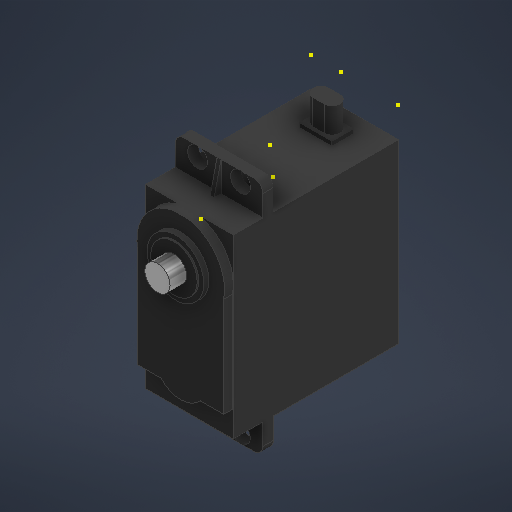
# Autodesk Inventor part: ServoMG99XX
Saved by Autodesk Inventor 2026.2 (Build 302298000, 298)
## iProperties
Created: 2026-07-16
Part Number: ServoMG99XX
Material: Generic
Document SubType Name: Modeling
Designer: Alexa
Density: 1 g/cm^3
Appearance: Default
Author: Alexa
Autodesk Inventor part; units mm, degrees
ref_plane "YZ Plane" through (0, 0, 0) normal (1, 0, 0) x (0, 1, 0)
ref_plane "XZ Plane" through (0, 0, 0) normal (0, 1, 0) x (-1, 0, 0)
ref_plane "XY Plane" through (0, 0, 0) normal (0, 0, 1) x (1, 0, 0)
sketch "Sketch1" plane through (0, 0, 0) normal (0, 0, 1) x (1, 0, 0)
  line L0 (0, 0) -> (-20, 0)
  line L1 (-20, 0) -> (-20, -54)
  line L2 (-20, -54) -> (0, -54)
  line L3 (0, -54) -> (0, 0)
  dimension "d0" = 20
  dimension "d1" = 54
  constraints: 8 end point, 2 parallel, 1 horizontal, 1 perpendicular
  measures "d0" distance of L2.end L1.end
  measures "d1" distance of L1.end L0.end
extrude "Extrusion1" add sketch "Sketch1" along normal blind 45
sketch "Sketch2" plane through (0, 0, 45) normal (0, 0, 1) x (1, 0, 0)
  point P0 (0, 0)
sketch "Sketch3" plane through (0, 0, 45) normal (0, 0, 1) x (1, 0, 0)
  point P0 (0, 0)
sketch "Sketch4" plane through (0, -54, 0) normal (1, 0, 0) x (0, 0, -1)
  line L0 (0, 54) -> (-28.52, 54)
  line L1 (-28.52, 54) -> (-28.52, 47.18)
  line L2 (-28.52, 47.18) -> (0, 47.18)
  line L3 (0, 47.18) -> (0, 54)
  line L4 (0, 54) -> (0, 0) projected
  line L5 (0, 0) -> (-28.52, 0)
  line L6 (-28.52, 0) -> (-28.52, 6.82)
  line L7 (-28.52, 6.82) -> (0, 6.82)
  line L8 (0, 6.82) -> (0, 0)
  line L9 (0, 54) -> (-45, 54) projected
  line L10 (-28.52, 47.18) -> (-32.52, 47.18)
  line L11 (-32.52, 47.18) -> (-32.52, 54)
  line L12 (-32.52, 54) -> (-28.52, 54)
  line L13 (-28.52, 54) -> (-28.52, 47.18)
  line L14 (0, 0) -> (-45, 0) projected
  line L15 (-28.52, 6.82) -> (-32.52, 6.82)
  line L16 (-32.52, 6.82) -> (-32.52, 0)
  line L17 (-32.52, 0) -> (-28.52, 0)
  line L18 (-28.52, 0) -> (-28.52, 6.82)
  line L19 (-32.52, 47.18) -> (-3.9, 47.18)
  line L20 (-3.9, 47.18) -> (-8.9, 47.18)
  line L21 (-8.9, 47.18) -> (-8.9, 54)
  line L22 (-8.9, 54) -> (-3.9, 54)
  line L23 (-3.9, 54) -> (-3.9, 47.18)
  line L24 (-32.52, 47.18) -> (-45, 47.18)
  line L25 (-45, 47.18) -> (-45, 54)
  line L26 (-45, 54) -> (-32.52, 54)
  line L27 (-32.52, 54) -> (-32.52, 47.18)
  line L28 (-32.52, 6.82) -> (-45, 6.82)
  line L29 (-45, 6.82) -> (-45, 0)
  line L30 (-45, 0) -> (-32.52, 0)
  line L31 (-32.52, 0) -> (-32.52, 6.82)
  line L32 (0, 47.18) -> (-41.22, 47.18)
  line L33 (-41.22, 47.18) -> (-41.22, 6.82)
  line L34 (-41.22, 6.82) -> (0, 6.82)
  line L35 (0, 6.82) -> (0, 47.18)
  line L36 (-45, 6.82) -> (-41.22, 6.82)
  line L37 (-41.22, 6.82) -> (-41.22, 40.24)
  line L38 (-41.22, 40.24) -> (-45, 40.24)
  line L39 (-45, 40.24) -> (-45, 6.82)
  line L40 (-45, 40.24) -> (-41.22, 40.24)
  line L41 (-41.22, 40.24) -> (-41.22, 34.46)
  line L42 (-41.22, 34.46) -> (-45, 34.46)
  line L43 (-45, 34.46) -> (-45, 40.24)
  line L44 (-45, 47.18) -> (-41.22, 47.18)
  line L45 (-41.22, 47.18) -> (-41.22, 40.24)
  line L46 (-41.22, 40.24) -> (-45, 40.24)
  line L47 (-45, 40.24) -> (-45, 47.18)
  line L48 (-45, 34.46) -> (-41.22, 34.46)
  line L49 (-41.22, 34.46) -> (-41.22, 6.82)
  line L50 (-41.22, 6.82) -> (-45, 6.82)
  line L51 (-45, 6.82) -> (-45, 34.46)
  line L52 (-45, 6.82) -> (0, 6.82)
  line L53 (0, 6.82) -> (0, 0)
  line L54 (0, 0) -> (-45, 0)
  line L55 (-45, 0) -> (-45, 6.82)
  line L56 (-45, 0) -> (-45, 54) projected
  line L57 (-45, 54) -> (-32.52, 54)
  line L58 (-32.52, 54) -> (-32.52, 47.18)
  line L59 (-32.52, 47.18) -> (-45, 47.18)
  line L60 (-45, 47.18) -> (-45, 54)
  line L61 (-28.52, 54) -> (-8.9, 54)
  line L62 (-8.9, 54) -> (-8.9, 47.18)
  line L63 (-8.9, 47.18) -> (-28.52, 47.18)
  line L64 (-28.52, 47.18) -> (-28.52, 54)
  line L65 (-3.9, 54) -> (0, 54)
  line L66 (0, 54) -> (0, 47.18)
  line L67 (0, 47.18) -> (-3.9, 47.18)
  line L68 (-3.9, 47.18) -> (-3.9, 54)
  point P0 (0, 6.82)
  dimension "d4" = 28.52
  dimension "d5" = 6.82
  dimension "d6" = 28.52
  dimension "d7" = 6.82
  dimension "d8" = 4
  dimension "d9" = 4
  dimension "d10" = 28.62
  dimension "d11" = 5
  dimension "d12" = 41.22
  dimension "d13" = 33.42
  dimension "d14" = 5.78
  constraints: 130 end point, 32 parallel, 16 horizontal, 16 perpendicular, 7 point on line, 1 other
  measures "d4" distance of L2.end L1.end
  measures "d5" distance of L1.end L0.end
  measures "d6" distance of L6.end L7.end
  measures "d7" distance of L5.end L6.end
  measures "d8" distance of L11.end L12.end
  measures "d9" distance of L17.end L16.end
  measures "d10" distance of L10.end L19.end
  measures "d11" distance of L21.end L22.end
  measures "d12" distance of L34.end L33.end
  measures "d13" distance of L37.end L36.end
  measures "d14" distance of L40.end L41.end
extrude "Extrusion2" cut sketch "Sketch4" against normal blind 45 contours L3 L2 L23 L0 | L21 L2 L1 L0 | L4 L5 L6 L7 | L11 L24 L25 L9 | L16 L14 L29 L28 | L28 L39 L42 L33 | L33 L38 L47 L24
sketch "Sketch5" plane through (0, -47.18, 0) normal (1, 0, 0) x (0, 0, -1)
  line L0 (-28.52, 40.36) -> (-28.52, 47.18) projected
  line L1 (-28.52, 47.18) -> (-30.92, 47.18)
  line L2 (-30.92, 47.18) -> (-30.92, 40.36)
  line L3 (-30.92, 40.36) -> (-28.52, 40.36)
  line L4 (-28.52, 40.36) -> (-28.52, 47.18)
  line L5 (-32.52, 47.18) -> (-32.52, 40.36) projected
  line L6 (-30.92, 47.18) -> (-32.52, 40.36)
  line L7 (-32.52, 40.36) -> (-32.52, 47.18)
  line L8 (-32.52, 47.18) -> (-30.92, 47.18)
  line L9 (-28.52, -6.82) -> (-32.52, -6.82) projected
  line L10 (-30.92, -6.82) -> (-30.92, 0.0312)
  line L11 (-30.92, 0.0312) -> (-32.5273, 0.0312)
  line L12 (-32.5273, 0.0312) -> (-30.92, -6.82)
  line L13 (-41.22, 0) -> (-32.52, 0) projected
  line L14 (-32.52, 0) -> (-32.52, -6.82)
  line L15 (-30.92, -6.82) -> (-32.52, 0)
  line L16 (-30.92, -6.82) -> (-32.52, -6.82)
  point P0 (0, 47.18)
  dimension "d17" = 2.4
  constraints: 26 end point, 4 perpendicular, 3 collinear, 2 parallel, 1 horizontal, 1 point on line, 1 vertical
  measures "d17" distance of L3.end L2.end
extrude "Extrusion3" cut sketch "Sketch5" against normal blind 45 contours L6 L5 L8 | L9 L14 L12
sketch "Sketch6" plane through (-20, -6.82, 32.52) normal (0, 0.2284, 0.9736) x (1, 0, 0)
  point P0 (20, 14.0674)
sketch "Sketch7" plane through (0, -6.82, 28.52) normal (0, 0, -1) x (-1, 0, 0)
  point P0 (0, 6.82)
sketch "Sketch8" plane through (-20, -47.18, 0) normal (-1, 0, 0) x (0, 0, 1)
  line L0 (28.52, -6.82) -> (30.92, -6.82) projected
  line L1 (41.22, 40.36) -> (32.52, 40.36) projected
  line L2 (32.52, 40.36) -> (30.92, 40.36)
  line L3 (30.92, 47.18) -> (32.52, 40.36) projected
  line L4 (30.92, 40.36) -> (30.92, 47.18)
  line L5 (30.92, 47.18) -> (32.52, 40.36)
  line L6 (32.52, 0) -> (41.22, 0) projected
  line L7 (32.52, 0) -> (30.92, 0)
  line L8 (30.92, 0) -> (30.92, -6.82)
  line L9 (32.52, 0) -> (30.92, -6.82)
  point P0 (0, 47.18)
  constraints: 12 end point, 2 perpendicular, 1 collinear, 1 horizontal, 1 parallel
extrude "Extrusion4" cut sketch "Sketch8" against normal blind 9.55
sketch "Sketch9" plane through (0, -47.18, 0) normal (1, 0, 0) x (0, 0, -1)
  line L0 (-28.52, 47.18) -> (-30.92, 47.18) projected
  line L1 (-32.52, 40.36) -> (-30.92, 40.36) projected
  line L2 (-30.92, 47.18) -> (-30.92, 40.36)
  line L3 (-30.92, 40.36) -> (-32.52, 40.36)
  line L4 (-32.52, 40.36) -> (-30.92, 47.18)
  line L5 (-30.92, 0) -> (-41.22, 0) projected
  line L6 (-30.92, -6.8061) -> (-30.92, 0)
  line L7 (-30.92, 0) -> (-32.52, 0)
  line L8 (-32.52, 0) -> (-30.92, -6.82)
  line L9 (-32.52, 0) -> (-30.92, 0)
  line L10 (-30.92, 0) -> (-30.92, -6.82)
  point P0 (0, 47.18)
  constraints: 16 end point, 3 collinear, 2 perpendicular, 2 point on line, 1 vertical
extrude "Extrusion5" cut sketch "Sketch9" against normal blind 9.55
sketch "Sketch10" plane through (0, -6.82, 8.9) normal (0, 0, 1) x (1, 0, 0)
  line L0 (0, 0) -> (-20, 0) projected
  line L1 (-20, 0) -> (-10, 0)
  line L2 (0, 0) -> (-20, 0) projected
  line L3 (-20, 6.82) -> (0, 6.82) projected
  line L4 (-10, 6.82) -> (-10, 0)
  line L5 (-10, 0) -> (-6.28, 0)
  line L6 (-6.28, 0) -> (-6.28, 6.82)
  line L7 (-6.28, 6.82) -> (-13.72, 6.82)
  line L8 (-13.72, 6.82) -> (-13.72, 0)
  line L9 (-13.72, 6.82) -> (-20, 6.82)
  line L10 (-20, 6.82) -> (-20, 0)
  line L11 (-20, 0) -> (-13.72, 0)
  line L12 (-13.72, 0) -> (-13.72, 6.82)
  line L13 (-6.28, 6.82) -> (0, 6.82)
  line L14 (0, 6.82) -> (0, 0)
  line L15 (0, 0) -> (-6.28, 0)
  line L16 (-6.28, 0) -> (-6.28, 6.82)
  line L17 (-13.72, 0) -> (-6.28, 0)
  line L18 (-6.28, 0) -> (-6.28, 1)
  line L19 (-6.28, 1) -> (-13.72, 1)
  line L20 (-13.72, 1) -> (-13.72, 0)
  line L21 (-10, 1) -> (-6.91, 1)
  line L22 (-6.91, 1) -> (-13.09, 1)
  line L23 (-13.09, 1) -> (-13.09, 6.82)
  line L24 (-13.09, 6.82) -> (-6.91, 6.82)
  line L25 (-6.91, 6.82) -> (-6.91, 1)
  point P0 (-6.28, 1)
  point P1 (-13.72, 1)
  point P2 (-13.09, 1)
  dimension "d24" = 3.72
  dimension "d25" = 7.44
  dimension "d26" = 1
  dimension "d27" = 3.09
  dimension "d28" = 6.18
  constraints: 46 end point, 8 parallel, 7 perpendicular, 7 point on line, 4 horizontal, 3 midpoint
  measures "d24" distance of L1.end L5.end
  measures "d25" distance of L6.end L7.end
  measures "d26" distance of L18.end L17.end
  measures "d27" distance of L21.start L21.end
  measures "d28" distance of L23.end L24.end
extrude "Extrusion6" cut sketch "Sketch10" against normal blind 9.55 contours L0 L6 L3 L14 | L19 L25 L3 L6 | L0 L10 L3 L8 | L8 L3 L23 L19
sketch "Sketch11" plane through (-13.09, -5.82, 8.9) normal (-1, 0, 0) x (0, 0, 1)
  line L0 (0, 0) -> (-5, 0) projected
  line L1 (-5, 0) -> (-2.5, 0)
  line L2 (0, 5.82) -> (-5, 5.82) projected
  line L3 (-5, 0) -> (-4.32, 0)
  line L4 (-4.32, 0) -> (-4.32, 5.82)
  line L5 (-4.32, 5.82) -> (-5, 5.82)
  line L6 (-5, 5.82) -> (-5, 0)
  line L7 (0, 0) -> (0, 5.82) projected
  line L8 (0, 0) -> (-0.68, 0)
  line L9 (-0.68, 0) -> (-0.68, 5.82)
  line L10 (-0.68, 5.82) -> (0, 5.82)
  line L11 (0, 5.82) -> (0, 0)
  point P0 (-8.9, 5.82)
  point P1 (-0.68, 5.82)
  point P2 (-0.68, 0)
  dimension "d31" = 0.68
  dimension "d32" = 0.68
  constraints: 18 end point, 4 parallel, 2 horizontal, 2 perpendicular, 2 point on line, 1 midpoint
  measures "d31" distance of L5.end L4.end
  measures "d32" distance of L9.end L10.end
extrude "Extrusion7" cut sketch "Sketch11" against normal blind 9.55 contours L0 L9 L2 L7 | L0 L6 L2 L4
sketch "Sketch12" plane through (-13.09, 0, 4.58) normal (0, 1, 0) x (1, 0, 0)
  line L0 (0, -3.64) -> (0, 0) projected
  line L1 (0, 0) -> (0, -1.82)
  line L2 (0, -1.82) -> (6.18, -1.82)
  line L3 (6.18, -3.64) -> (6.18, 0) projected
  line L4 (0, 0) -> (1.82, 0)
  line L5 (1.82, 0) -> (1.82, -1.82)
  line L6 (1.82, -1.82) -> (0, -1.82)
  line L7 (0, -1.82) -> (0, 0)
  line L8 (6.18, 0) -> (4.36, 0)
  line L9 (4.36, 0) -> (4.36, -1.82)
  line L10 (4.36, -1.82) -> (6.18, -1.82)
  line L11 (6.18, -1.82) -> (6.18, 0)
  circle A0 centre (1.82, -1.82) radius 1.82
  circle A1 centre (4.36, -1.82) radius 1.82
  point P0 (13.09, 4.58)
  point P1 (0, -1.82)
  point P2 (6.18, -1.82)
  dimension "d35" = 1.82
  dimension "d36" = 1.82
  constraints: 20 end point, 4 parallel, 2 coincident, 2 horizontal, 2 midpoint, 2 perpendicular, 2 point on line, 6 other
  measures "d35" distance of L5.end L6.end
  measures "d36" distance of L10.end L9.end
sketch "Sketch13" plane through (-13.09, -5.82, 4.58) normal (-1, 0, 0) x (0, 0, 1)
  point P0 (-4.58, 5.82)
sketch "Sketch14" plane through (-13.09, 0, 4.58) normal (0, 1, 0) x (1, 0, 0)
  line L0 (0, -3.64) -> (0, 0) projected
  line L1 (0, -3.64) -> (2.0031, -3.64)
  line L2 (0, -3.64) -> (6.18, -3.64) projected
  line L3 (2.0031, -3.64) -> (6.2061, -3.64)
  line L4 (6.18, -3.64) -> (6.18, 0) projected
  line L5 (6.18, -3.64) -> (6.18, 0)
  line L6 (6.18, 0) -> (0, 0)
  point P0 (13.09, 4.58)
  constraints: 8 end point, 2 point on line, 1 collinear, 1 perpendicular
sketch "Sketch15" plane through (-13.09, -5.82, 4.58) normal (-1, 0, 0) x (0, 0, 1)
  point P0 (-4.58, 5.82)
sketch "Sketch16" plane through (-13.09, -5.82, 4.58) normal (-1, 0, 0) x (0, 0, 1)
  point P0 (-4.58, 5.82)
sketch "Sketch17" plane through (-13.09, 0, 4.58) normal (0, 1, 0) x (1, 0, 0)
  point P0 (13.09, 4.58)
extrude "Extrusion8" cut sketch "Sketch12" against normal blind 5.82 contours L0 L4 A0 | A1 L8 L3
sketch "Sketch18" plane through (-13.09, 0, 8.22) normal (0, 1, 0) x (1, 0, 0)
  arc A0 (1.82, 3.64) -> (0, 1.82) centre (1.82, 1.82) ccw projected
  circle A1 centre (1.82, 1.82) radius 1.82
  line L0 (0, 0) -> (6.18, 0) projected
  arc A2 (6.18, 1.82) -> (4.36, 3.64) centre (4.36, 1.82) ccw projected
  circle A3 centre (4.36, 1.82) radius 1.82
  line L1 (0, 0) -> (0, 1.82) projected
  line L2 (0, 1.82) -> (0, 0)
  line L3 (0, 0) -> (1.82, 0)
  line L4 (6.18, 0) -> (6.18, 1.82) projected
  line L5 (4.36, 0) -> (6.18, 0)
  line L6 (6.18, 0) -> (6.18, 1.82)
  point P0 (13.09, 8.22)
  constraints: 8 end point, 3 perpendicular, 2 coincident, 2 horizontal, 2 point on circle, 2 point on line, 2 tangent, 1 centre point, 1 vertical, 3 other
extrude "Extrusion9" cut sketch "Sketch18" against normal blind 5.82 contours A1 L0 L1 | A3 L4 L0
extrude "Extrusion10" add sketch "Sketch14" along normal blind 1
sketch "Sketch19" plane through (-13.09, 1, 4.58) normal (0, 1, 0) x (1, 0, 0)
  line L0 (1.82, 0) -> (0, 0) projected
  line L1 (4.36, -3.64) -> (6.18, -3.64) projected
  line L2 (0, 0) -> (6.18, 0)
  line L3 (6.18, 0) -> (6.18, -3.64)
  line L4 (6.18, -3.64) -> (0, -3.64)
  line L5 (0, -3.64) -> (0, 0)
  point P0 (13.09, 4.58)
  constraints: 8 end point, 2 parallel, 1 horizontal, 1 perpendicular
extrude "Extrusion11" cut sketch "Sketch19" against normal blind 1
sketch "Sketch20" plane through (-20, -54, 30.92) normal (0, 0, 1) x (1, 0, 0)
  line L0 (9.9498, 0) -> (9.9498, 54)
  line L1 (9.9498, 54) -> (9.9498, 51.75)
  line L2 (9.9498, 51.75) -> (7.2998, 51.75)
  line L3 (7.2998, 51.75) -> (12.5998, 51.75)
  line L4 (7.2998, 51.75) -> (5.0498, 51.75)
  line L5 (12.5998, 51.75) -> (14.8498, 51.75)
  circle A0 centre (5.0498, 51.75) radius 2.25
  line L6 (20, 54) -> (0, 54) projected
  circle A1 centre (14.8498, 51.75) radius 2.25
  line L7 (0, 6.82) -> (0, 0) projected
  line L8 (0, 0) -> (0, 27)
  line L9 (0, 6.82) -> (0, 34.46) projected
  line L10 (0, 27) -> (20, 27)
  circle A2 centre (5.0498, 2.25) radius 2.25
  circle A3 centre (14.8498, 2.25) radius 2.25
  dimension "d45" = 2.25
  dimension "d46" = 2.65
  dimension "d47" = 5.3
  dimension "d48" = 2.25
  dimension "d49" = 2.25
  constraints: 16 end point, 4 centre point, 4 point on line, 2 coincident, 2 horizontal, 2 symmetric about line, 2 tangent, 1 perpendicular, 1 vertical, 2 other
  measures "d45" distance of L0.end L1.end
  measures "d46" distance of L1.end L2.end
  measures "d47" distance of L2.end L3.end
  measures "d48" distance of L2.end L4.end
  measures "d49" distance of L3.end L5.end
extrude "Extrusion12" cut sketch "Sketch20" against normal blind 5 contours A0 | A1 | A2 | A3
fillet "Fillet1" radius 2 1 edges at (-20, -54, 29.72)
fillet "Fillet2" radius 2 1 edges at (0, -54, 29.72)
fillet "Fillet3" radius 2 1 edges at (-20, 0, 29.72)
fillet "Fillet4" radius 2 1 edges at (0, 0, 29.72)
sketch "Sketch21" plane through (-20, -47.18, 0) normal (-1, 0, 0) x (0, 0, 1)
  point P0 (0, 47.18)
sketch "Sketch22" plane through (0, 0, 45) normal (0, 0, 1) x (1, 0, 0)
  line L0 (0, -13.76) -> (-20, -13.76) projected
  line L1 (-10, -13.76) -> (-10, -16.65)
  line L2 (0, -47.18) -> (0, -6.82) projected
  circle A0 centre (-10, -16.65) radius 2.89
  line L3 (-20, -13.76) -> (0, -13.76)
  line L4 (0, -13.76) -> (0, -19.54)
  line L5 (0, -19.54) -> (-20, -19.54)
  line L6 (-20, -19.54) -> (-20, -13.76)
  point P0 (0, 0)
  point P1 (-10, -19.54)
  dimension "d56" = 2.89
  dimension "d57" = 5.78
  constraints: 10 end point, 3 parallel, 1 centre point, 1 coincident, 1 horizontal, 1 midpoint, 1 perpendicular, 1 point on line
  measures "d56" distance of L1.start L1.end
  measures "d57" diameter of A0
extrude "Extrusion13" cut sketch "Sketch22" against normal blind 3.78 contours L2 L5 A0 L0 | A0 L5 L6 L0
sketch "Sketch23" plane through (0, -47.18, 41.22) normal (0, 0, 1) x (1, 0, 0)
  circle A0 centre (-10, 30.53) radius 2.89 projected
  circle A1 centre (-10, 30.53) radius 5.3
  line L0 (0, 40.36) -> (-20, 40.36) projected
  line L1 (0, 0) -> (0, 40.36) projected
  line L2 (-20, 40.36) -> (0, 40.36)
  line L3 (0, 40.36) -> (0, 0)
  line L4 (0, 0) -> (-20, 0)
  line L5 (-20, 0) -> (-20, 40.36)
  point P0 (0, 47.18)
  dimension "d60" = 10.6
  constraints: 8 end point, 2 parallel, 1 centre point, 1 coincident, 1 horizontal, 1 perpendicular
  measures "d60" diameter of A1
extrude "Extrusion14" cut sketch "Sketch23" against normal blind 0.34 contours L1 L4 L5 L0
sketch "Sketch24" plane through (0, -47.18, 40.88) normal (0, 0, 1) x (1, 0, 0)
  circle A0 centre (-10, 30.53) radius 2.89 projected
  circle A1 centre (-10, 30.53) radius 6.45
  line L0 (-20, 40.36) -> (-10.45, 40.36) projected
  line L1 (0, 40.36) -> (0, 0) projected
  line L2 (-20, 40.36) -> (0, 40.36)
  line L3 (0, 40.36) -> (0, 0)
  line L4 (0, 0) -> (-20, 0)
  line L5 (-20, 0) -> (-20, 40.36)
  point P0 (0, 47.18)
  dimension "d63" = 12.9
  constraints: 8 end point, 2 parallel, 1 centre point, 1 coincident, 1 horizontal, 1 perpendicular
  measures "d63" diameter of A1
extrude "Extrusion15" cut sketch "Sketch24" against normal blind 1.2 contours L0 L2 L1 L4 L5
sketch "Sketch25" plane through (0, -47.18, 39.68) normal (0, 0, 1) x (1, 0, 0)
  circle A0 centre (-10, 30.53) radius 2.89 projected
  circle A1 centre (-10, 30.53) radius 10
  line L0 (0, 0) -> (0, 40.36) projected
  line L1 (-20, 40.36) -> (-20, 0) projected
  line L2 (-20, 40.36) -> (0, 40.36)
  line L3 (0, 40.36) -> (0, 0)
  line L4 (0, 0) -> (-20, 0)
  line L5 (-20, 0) -> (-20, 40.36)
  line L6 (0, 0) -> (-0.2, 0)
  line L7 (-0.2, 0) -> (-0.2, 30.53)
  line L8 (0, 0) -> (0, 0.2)
  line L9 (0, 0.2) -> (-20, 0.2)
  line L10 (-20, 0) -> (-19.8, 0)
  line L11 (-19.8, 0) -> (-19.8, 39.3573)
  line L12 (0, 0) -> (0, 5.8)
  line L13 (0, 5.8) -> (-20, 5.8)
  line L14 (-10, 5.8) -> (-10, 9.8)
  circle A2 centre (-10, 9.8) radius 6
  line L15 (-20, 0) -> (-20, 0.2)
  line L16 (0, 0) -> (0, 0.2)
  line L17 (0, 0) -> (-9.55, 0) projected
  point P0 (0, 47.18)
  point P1 (0, 30.53)
  point P2 (-0.2, 28.54)
  point P3 (-0.2, 5.8)
  point P4 (-5.5279, 5.8)
  point P5 (-14.4721, 5.8)
  point P6 (-19.8, 5.8)
  point P7 (-19.8, 28.54)
  point P8 (-20, 30.53)
  point P9 (-11.8361, 40.36)
  point P10 (-8.1639, 40.36)
  dimension "d66" = 0.2
  dimension "d67" = 0.2
  dimension "d68" = 0.2
  dimension "d69" = 5.8
  dimension "d70" = 4
  dimension "d71" = 12
  constraints: 30 end point, 6 point on line, 5 perpendicular, 3 parallel, 2 centre point, 2 coincident, 2 vertical, 1 horizontal, 1 midpoint, 1 tangent
  measures "d66" distance of L0.start L6.end
  measures "d67" distance of L0.start L8.end
  measures "d68" distance of L4.end L10.end
  measures "d69" distance of L0.start L12.end
  measures "d70" distance of L14.start L14.end
  measures "d71" diameter of A2
extrude "Extrusion16" cut sketch "Sketch25" against normal blind 2 contours L0 L13 L7 A1 | A1 L2 L0 | L0 L9 L7 L13 | A1 L1 L2 | L11 L13 L1 A1 | L7 L9 L11 L13 A2 | L0 L4 L7 L9 | L11 L9 L1 L13 | L7 L4 L11 L9 | L11 L4 L1 L9
body "Solid1"
